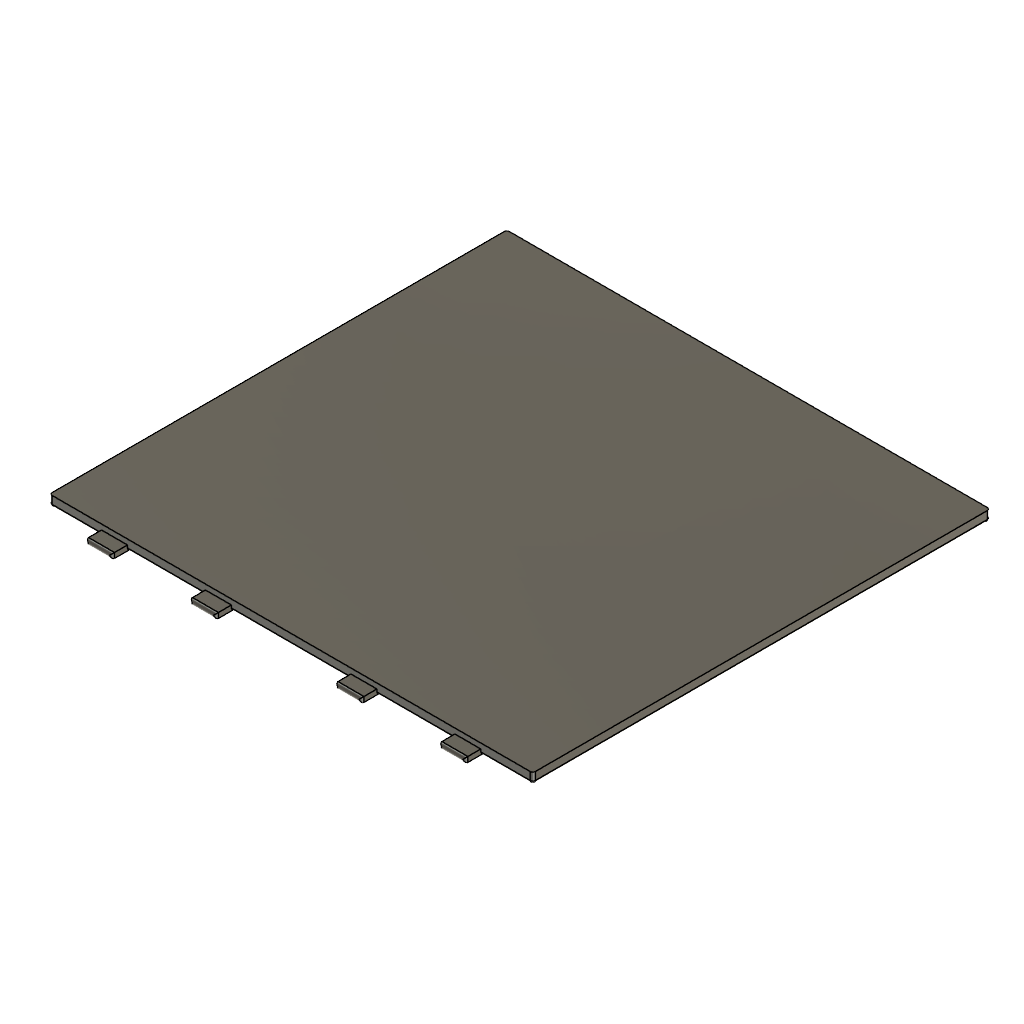
Doomsday deck (Autodesk Fusion 360 archive; units mm, degrees)
design "battery case"
part number: 2026-10-02-18-48-10-516
Autodesk Fusion 360 part; units mm, degrees
sketch "Sketch1" plane through (0, 0, 0) normal (0, 0, 1) x (1, 0, 0)
  line L0 (0, 0) -> (93, 0)
  line L1 (93, 0) -> (93, 88)
  line L2 (93, 88) -> (0, 88)
  line L3 (0, 88) -> (0, 0)
  dimension "d1" = 93
  dimension "d2" = 88
  constraint horizontal L0
  constraint vertical L1
  constraint horizontal L2
  constraint vertical L3
  constraint coincident L0.start L3.end
  measures "d1" distance of L0.start L0.end
  measures "d2" distance of L0.start L2.end
extrude "Extrude1" add sketch "Sketch1" along normal blind 2
sketch "Sketch2" plane through (0, 0, 0) normal (0, -1, 0) x (1, 0, 0)
  line L0 (0, 0) -> (93, 0)
  line L1 (93, 0) -> (93, 2)
  line L2 (93, 2) -> (0, 2)
  line L3 (0, 2) -> (0, 0)
  line L4 (0, 0) -> (10, 0) construction
  line L5 (10, 0) -> (15, 0)
  line L6 (15, 0) -> (15, 1)
  line L7 (15, 1) -> (10, 1)
  line L8 (10, 1) -> (10, 0)
  line L9 (15, 0) -> (30, 0) construction
  line L10 (30, 0) -> (35, 0)
  line L11 (35, 0) -> (35, 1)
  line L12 (35, 1) -> (30, 1)
  line L13 (30, 1) -> (30, 0)
  line L14 (93, 0) -> (83, 0) construction
  line L15 (83, 0) -> (78, 0)
  line L16 (78, 0) -> (78, 1)
  line L17 (78, 1) -> (83, 1)
  line L18 (83, 1) -> (83, 0)
  line L19 (78, 0) -> (63, 0) construction
  line L20 (63, 0) -> (58, 0)
  line L21 (58, 0) -> (58, 1)
  line L22 (58, 1) -> (63, 1)
  line L23 (63, 1) -> (63, 0)
  dimension "d5" = 10
  dimension "d7" = 1
  dimension "d8" = 15
  dimension "d10" = 1
  dimension "d12" = 5
  dimension "d13" = 1
  dimension "d16" = 1
  constraint coincident L0.start L3.end
  constraint perpendicular L3 L4
  constraint vertical L6
  constraint horizontal L7
  constraint vertical L8
  constraint perpendicular L6 L9
  constraint vertical L11
  constraint horizontal L12
  constraint vertical L13
  constraint coincident L0.end L1.start
  constraint perpendicular L1 L14
  constraint horizontal L15
  constraint vertical L16
  constraint horizontal L17
  constraint vertical L18
  constraint perpendicular L16 L19
  constraint horizontal L20
  constraint vertical L21
  constraint horizontal L22
  constraint vertical L23
  measures "d5" distance of L0.start L4.end
  measures "d7" distance of L4.end L7.end
  measures "d8" distance of L5.end L9.end
  measures "d10" distance of L9.end L12.end
  measures "d12" distance of L14.end L15.end
  measures "d13" distance of L14.end L17.end
  measures "d16" distance of L19.end L22.end
extrude "Extrude2" add sketch "Sketch2" along normal blind 3 contours L0 L5 L6 L7 L8 | L0 L10 L11 L12 L13 | L0 L15 L16 L17 L18 | L0 L20 L21 L22 L23
fillet "Fillet2" radius 0.5 16 edges at (12.5, -3, 0) (10, -3, 0.5) (12.5, -3, 1) (15, -3, 0.5) (32.5, -3, 1) (30, -3, 0.5) (32.5, -3, 0) (35, -3, 0.5) (60.5, -3, 1) (58, -3, 0.5) (60.5, -3, 0) (63, -3, 0.5) (80.5, -3, 1) (78, -3, 0.5) (80.5, -3, 0) (83, -3, 0.5)
fillet "Fillet3" radius 0.5 8 edges at (88, 0, 0) (70.5, 0, 0) (46.5, 0, 0) (22.5, 0, 0) (5, 0, 0) (0, 44, 0) (46.5, 88, 0) (93, 44, 0)
fillet "Fillet4" radius 0.5 8 edges at (92.8536, 0.1464, 0.1464) (93, 0, 1.25) (92.8536, 87.8536, 0.1464) (93, 88, 1.25) (0.1464, 87.8536, 0.1464) (0, 88, 1.25) (0.1464, 0.1464, 0.1464) (0, 0, 1.25)
